testHingeBottom (Autodesk Fusion 360 design; units mm, degrees)
Autodesk Fusion 360 part; units mm, degrees
sketch "Sketch1" plane through (0, 0, 0) normal (0, 1, 0) x (1, 0, 0)
  circle A0 centre (0, 0) radius 20
  dimension "d1" = 40
  constraint coincident A0.centre origin
  measures "d1" diameter of A0
extrude "Extrude1" add sketch "Sketch1" along normal blind 20
sketch "Sketch2" plane through (0, 20, 0) normal (0, 1, 0) x (-1, 0, 0)
  circle A0 centre (0, 0) radius 20
  line L0 (0, 0) -> (-20, 0)
  line L1 (-20, 0) -> (-25, 0)
  line L2 (-25, 0) -> (-25, 2.5)
  line L3 (-25, 0) -> (-25, -2.5)
  line L4 (-25, -2.5) -> (-19.8431, -2.5)
  line L5 (-25, 2.5) -> (-19.8431, 2.5)
  line L6 (-25, -2.5) -> (-25, -2.6)
  line L7 (-25, 2.5) -> (-25, 2.6)
  line L8 (-25, 2.6) -> (-19.8303, 2.6)
  line L9 (-25, -2.6) -> (-19.8303, -2.6)
  line L10 (-25, 2.6) -> (-25, 7.6)
  line L11 (-25, 7.6) -> (-18.4997, 7.6)
  line L12 (-25, -2.6) -> (-25, -7.6)
  line L13 (-25, -7.6) -> (-18.4997, -7.6)
  dimension "d4" = 5
  dimension "d5" = 2.5
  dimension "d6" = 2.5
  dimension "d7" = 0.1
  dimension "d8" = 0.1
  dimension "d9" = 5
  dimension "d10" = 5
  constraint coincident A0.centre L0.start
  constraint coincident A0 L0.end
  constraint horizontal L0
  constraint parallel L0 L1
  constraint perpendicular L1 L2
  constraint perpendicular L1 L3
  constraint coincident A0 L4.end
  constraint horizontal L4
  constraint coincident A0 L5.end
  constraint horizontal L5
  constraint vertical L6
  constraint perpendicular L5 L7
  constraint coincident A0 L8.end
  constraint horizontal L8
  constraint coincident A0 L9.end
  constraint horizontal L9
  constraint perpendicular L8 L10
  constraint coincident A0 L11.end
  constraint horizontal L11
  constraint perpendicular L9 L12
  constraint coincident A0 L13.end
  constraint horizontal L13
  measures "d4" distance of L0.end L1.end
  measures "d5" distance of L1.end L2.end
  measures "d6" distance of L1.end L3.end
  measures "d7" distance of L3.end L6.end
  measures "d8" distance of L2.end L7.end
  measures "d9" distance of L7.end L10.end
  measures "d10" distance of L6.end L12.end
extrude "Extrude2" add sketch "Sketch2" along normal blind 2.5 and the other way blind 2.5 contours A0 L8 L10 L11 | A0 L9 L12 L13
fillet "Fillet1" radius 2.5 6 edges at (19.3274, 22.5, 5.1432) (25, 22.5, 5.1) (25, 17.5, 5.1) (19.3274, 22.5, -5.1432) (25, 22.5, -5.1) (25, 17.5, -5.1)
sketch "Sketch3" plane through (0, 0, 7.6) normal (0, 0, 1) x (1, 0, 0)
  arc A0 (22.5, 17.5) -> (22.5, 22.5) centre (22.5, 20) ccw
  line L0 (22.5, 22.5) -> (21.1776, 22.5)
  spline S0 degree 3 poles (18.4997, 20) (18.4997, 20.3014) (18.5744, 20.6553) (18.8192, 21.2197) (19.0367, 21.527) (19.5, 21.9697) (19.8315, 22.1799) (20.4469, 22.4247) (20.8422, 22.5) (21.1776, 22.5) knots 0.764054 0.764054 0.764054 0.764054 0.854482 0.854482 0.948604 0.948604 1.046719 1.046719 1.147322 1.147322 1.147322 1.147322
  line L1 (18.4997, 20) -> (18.4997, 17.5)
  line L2 (18.4997, 17.5) -> (22.5, 17.5)
  circle A1 centre (22.5, 20) radius 1
  dimension "d16" = 2
  constraint concentric A0 A1
  measures "d16" diameter of A1
extrude "Extrude3" cut sketch "Sketch3" against normal blind 15.2 contours A1
chamfer "Chamfer1" distance 1 angle 45 2 edges at (21.5677, 19.6384, -7.6) (21.5677, 20.3616, 7.6) tangent chain off
fillet "Fillet2" radius 0.5 2 edges at (21.5677, 19.6384, 2.6) (21.5677, 20.3616, -2.6)
